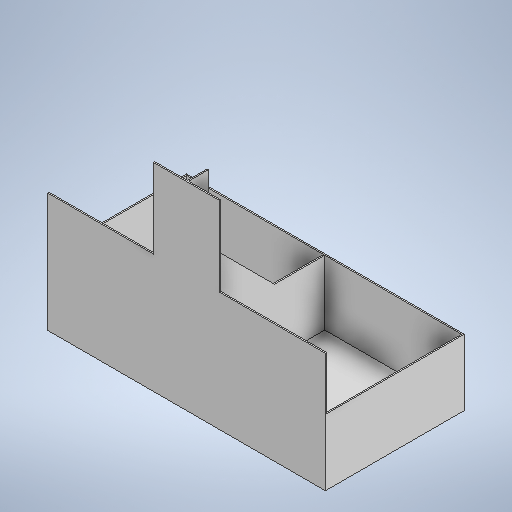
# Autodesk Inventor part: RDS-GHN500-1000 Container
Saved by Autodesk Inventor 2026 (Build 300175000, 175)
## iProperties
Created: 2026-10-27
Part Number: RDS-GHN500-1000 Container
Material: Типовые
Document SubType Name: Modeling
Designer: user
Density: 1 g/cm^3
Appearance: По умолчанию
Author: user
Autodesk Inventor part; units mm, degrees
ref_plane "YZ Plane" through (0, 0, 0) normal (1, 0, 0) x (0, 1, 0)
ref_plane "XZ Plane" through (0, 0, 0) normal (0, 1, 0) x (-1, 0, 0)
ref_plane "XY Plane" through (0, 0, 0) normal (0, 0, 1) x (1, 0, 0)
sketch "Эскиз1" plane through (0, 0, 0) normal (0, 1, 0) x (-1, 0, 0)
  line L0 (1050, -525) -> (-1050, -525)
  line L1 (-1050, -525) -> (-1050, 525)
  line L2 (-1050, 525) -> (1050, 525)
  line L3 (1050, 525) -> (1050, -525)
  line L4 (1050, -525) -> (-1050, 525) construction
  line L5 (-1050, -525) -> (1050, 525) construction
  point P0 (0, 0)
  dimension "d0" = 2100
  dimension "d1" = 1050
  constraints: 12 end point, 2 midpoint, 2 parallel, 1 horizontal, 1 perpendicular
  measures "d0" distance of L1.end L2.end
  measures "d1" distance of L0.end L1.end
extrude "Выдавливание1" add sketch "Эскиз1" along normal blind 10
sketch "Эскиз2" plane through (0, 10, 0) normal (0, 1, 0) x (1, 0, 0)
  line L0 (-1050, 525) -> (-1050, -525) projected
  line L1 (-1050, -525) -> (1050, -525) projected
  line L2 (-1050, 525) -> (1050, 525)
  line L3 (1050, 525) -> (1050, -525)
  line L4 (1050, -525) -> (-1050, -525)
  line L5 (-1050, -525) -> (-1050, 525)
  line L6 (-1040, -515) -> (1040, -515)
  line L7 (1040, -515) -> (1040, 515)
  line L8 (1040, 515) -> (-1040, 515)
  line L9 (-1040, 515) -> (-1040, -515)
  line L10 (-1040, -515) -> (1040, 515) construction
  line L11 (1040, -515) -> (-1040, 515) construction
  line L12 (-5, 515) -> (5, 515)
  line L13 (5, 515) -> (5, -515)
  line L14 (5, -515) -> (-5, -515)
  line L15 (-5, -515) -> (-5, 515)
  point P0 (0, 0)
  dimension "d4" = 2080
  dimension "d5" = 1030
  dimension "d6" = 10
  dimension "d7" = 5
  constraints: 28 end point, 6 parallel, 3 horizontal, 3 perpendicular, 2 midpoint, 2 point on line
  measures "d4" distance of L8.end L7.end
  measures "d5" distance of L7.end L6.end
  measures "d6" distance between parallel lines of L13 L15
  measures "d7" distance from line of L15 point (0, 0)
extrude "Выдавливание2" add sketch "Эскиз2" along normal blind 490 contours L2 L3 L1 L0 | L15 L8 L13 L6
sketch "Эскиз3" plane through (0, 500, 0) normal (0, 1, 0) x (1, 0, 0)
  line L0 (-1050, 525) -> (-1050, -525) projected
  line L1 (1050, -525) -> (1050, 525) projected
  line L2 (-1050, -525) -> (1050, -525)
  line L3 (1050, -525) -> (1050, -515)
  line L4 (1050, -515) -> (-1050, -515)
  line L5 (-1050, -515) -> (-1050, -525)
  point P0 (0, 0)
  dimension "d10" = 10
  constraints: 8 end point, 2 parallel, 1 horizontal, 1 perpendicular, 1 point on line
  measures "d10" distance between parallel lines of L2 L4
extrude "Выдавливание3" add sketch "Эскиз3" along normal blind 400
sketch "Эскиз4" plane through (0, 900, 0) normal (0, 1, 0) x (1, 0, 0)
  line L0 (-1040, -515) -> (-5, -515) projected
  line L1 (-1050, -525) -> (1050, -525) projected
  line L2 (-250, -515) -> (250, -515)
  line L3 (250, -515) -> (250, -525)
  line L4 (250, -525) -> (-250, -525)
  line L5 (-250, -525) -> (-250, -515)
  point P0 (0, 0)
  point P1 (-250, -525)
  point P2 (-5, -515)
  dimension "d13" = 500
  dimension "d14" = 250
  constraints: 8 end point, 2 parallel, 2 point on line, 1 horizontal, 1 perpendicular
  measures "d13" distance of L2.start L2.end
  measures "d14" distance from line of point (0, 0) L5
extrude "Выдавливание4" add sketch "Эскиз4" along normal blind 600
sketch "Эскиз5" plane through (5, 10, 515) normal (1, 0, 0) x (0, 0, -1)
  line L0 (0, 1490) -> (-10, 1490) projected
  line L1 (0, 1490) -> (150, 1490)
  line L2 (150, 1490) -> (150, 990)
  line L3 (150, 990) -> (650, 490)
  line L4 (1030, 490) -> (0, 490) projected
  line L5 (0, 890) -> (0, 1490) projected
  line L6 (0, 1490) -> (0, 490)
  line L7 (0, 490) -> (650, 490)
  point P0 (515, -10)
  point P1 (0, 890)
  point P2 (1115, 490)
  point P3 (65, 490)
  point P4 (65, 490)
  dimension "d17" = 150
  dimension "d18" = 500
  dimension "d19" = 135
  constraints: 10 end point, 2 collinear, 1 horizontal, 1 perpendicular, 1 point on line
  measures "d17" distance of L0.start L1.end
  measures "d18" distance of L1.end L2.end
  measures "d19" angle of L3 L2
extrude "Выдавливание5" add sketch "Эскиз5" against normal blind 10
